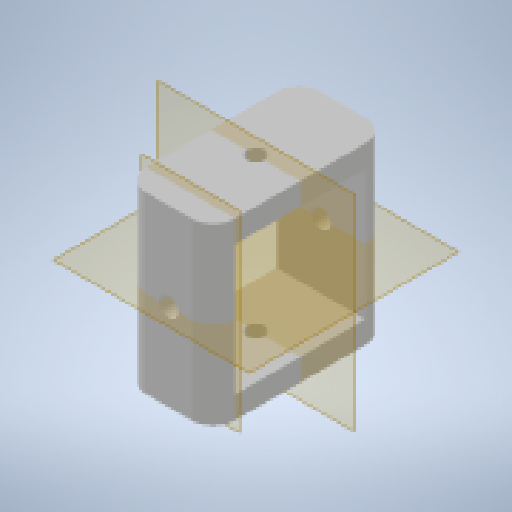
# Autodesk Inventor part: SPIDER GEAR BOX
Saved by Autodesk Inventor 2026.3 (Build 303398000, 398)
## iProperties
Created: 2026-10-21
Part Number: SPIDER GEAR BOX
Material: Generic
Document SubType Name: Modeling
Designer: Salim
Density: 1 g/cm^3
Appearance: Smooth - Red
Author: Salim
Autodesk Inventor part; units mm, degrees
ref_plane "YZ Plane" through (0, 0, 0) normal (1, 0, 0) x (0, 1, 0)
ref_plane "XZ Plane" through (0, 0, 0) normal (0, 1, 0) x (-1, 0, 0)
ref_plane "XY Plane" through (0, 0, 0) normal (0, 0, 1) x (1, 0, 0)
ref_plane "Work Plane5" through (12.266619, -6.690883, -0.784853) normal (0, 0, 1) x (1, 0, 0)
sketch "Sketch1" plane through (12.266619, -6.690883, -0.784853) normal (0, 0, 1) x (1, 0, 0)
  circle A0 centre (-12.266619, 0) radius 2.15
  line L0 (-2.266619, -14.6335) -> (-22.266619, -14.6335)
  line L1 (-22.266619, -14.6335) -> (-22.266619, 14.6335)
  line L2 (-22.266619, 14.6335) -> (-2.266619, 14.6335)
  line L3 (-2.266619, 14.6335) -> (-2.266619, -14.6335)
  line L4 (-2.266619, -14.6335) -> (-22.266619, 14.6335) construction
  line L5 (-22.266619, -14.6335) -> (-2.266619, 14.6335) construction
  arc A1 (-11.792035, 12.257435) -> (-12.741203, 12.257435) centre (-12.266619, 0) ccw
  arc A2 (-12.741203, 12.257435) -> (-14.980664, 11.962604) centre (-12.266619, 0) ccw
  arc A3 (-14.980664, 11.962604) -> (-15.89749, 11.716942) centre (-12.266619, 0) ccw
  arc A4 (-15.89749, 11.716942) -> (-17.984335, 10.852542) centre (-12.266619, 0) ccw
  arc A5 (-17.984335, 10.852542) -> (-18.806338, 10.377958) centre (-12.266619, 0) ccw
  arc A6 (-18.806338, 10.377958) -> (-20.598353, 9.002897) centre (-12.266619, 0) ccw
  arc A7 (-20.598353, 9.002897) -> (-21.269516, 8.331734) centre (-12.266619, 0) ccw
  arc A8 (-21.269516, 8.331734) -> (-22.644577, 6.539719) centre (-12.266619, 0) ccw
  arc A9 (-22.644577, 6.539719) -> (-23.119161, 5.717716) centre (-12.266619, 0) ccw
  arc A10 (-23.119161, 5.717716) -> (-23.983561, 3.630871) centre (-12.266619, 0) ccw
  arc A11 (-23.983561, 3.630871) -> (-24.229223, 2.714045) centre (-12.266619, 0) ccw
  arc A12 (-24.229223, 2.714045) -> (-24.524054, 0.474584) centre (-12.266619, 0) ccw
  arc A13 (-24.524054, 0.474584) -> (-24.524054, -0.474584) centre (-12.266619, 0) ccw
  arc A14 (-24.524054, -0.474584) -> (-24.229223, -2.714045) centre (-12.266619, 0) ccw
  arc A15 (-24.229223, -2.714045) -> (-23.983561, -3.630871) centre (-12.266619, 0) ccw
  arc A16 (-23.983561, -3.630871) -> (-23.119161, -5.717716) centre (-12.266619, 0) ccw
  arc A17 (-23.119161, -5.717716) -> (-22.644577, -6.539719) centre (-12.266619, 0) ccw
  arc A18 (-22.644577, -6.539719) -> (-21.269516, -8.331734) centre (-12.266619, 0) ccw
  arc A19 (-21.269516, -8.331734) -> (-20.598353, -9.002897) centre (-12.266619, 0) ccw
  arc A20 (-20.598353, -9.002897) -> (-18.806338, -10.377958) centre (-12.266619, 0) ccw
  arc A21 (-18.806338, -10.377958) -> (-17.984335, -10.852542) centre (-12.266619, 0) ccw
  arc A22 (-17.984335, -10.852542) -> (-15.89749, -11.716942) centre (-12.266619, 0) ccw
  arc A23 (-15.89749, -11.716942) -> (-14.980664, -11.962604) centre (-12.266619, 0) ccw
  arc A24 (-14.980664, -11.962604) -> (-12.741203, -12.257435) centre (-12.266619, 0) ccw
  arc A25 (-12.741203, -12.257435) -> (-11.792035, -12.257435) centre (-12.266619, 0) ccw
  arc A26 (-11.792035, -12.257435) -> (-9.552574, -11.962604) centre (-12.266619, 0) ccw
  arc A27 (-9.552574, -11.962604) -> (-8.635748, -11.716942) centre (-12.266619, 0) ccw
  arc A28 (-8.635748, -11.716942) -> (-6.548903, -10.852542) centre (-12.266619, 0) ccw
  arc A29 (-6.548903, -10.852542) -> (-5.7269, -10.377958) centre (-12.266619, 0) ccw
  arc A30 (-5.7269, -10.377958) -> (-3.934885, -9.002897) centre (-12.266619, 0) ccw
  arc A31 (-3.934885, -9.002897) -> (-3.263722, -8.331734) centre (-12.266619, 0) ccw
  arc A32 (-3.263722, -8.331734) -> (-1.888661, -6.539719) centre (-12.266619, 0) ccw
  arc A33 (-1.888661, -6.539719) -> (-1.414077, -5.717716) centre (-12.266619, 0) ccw
  arc A34 (-1.414077, -5.717716) -> (-0.549677, -3.630871) centre (-12.266619, 0) ccw
  arc A35 (-0.549677, -3.630871) -> (-0.304015, -2.714045) centre (-12.266619, 0) ccw
  arc A36 (-0.304015, -2.714045) -> (-0.009184, -0.474584) centre (-12.266619, 0) ccw
  arc A37 (-0.009184, -0.474584) -> (-0.009184, 0.474584) centre (-12.266619, 0) ccw
  arc A38 (-0.009184, 0.474584) -> (-0.304015, 2.714045) centre (-12.266619, 0) ccw
  arc A39 (-0.304015, 2.714045) -> (-0.549677, 3.630871) centre (-12.266619, 0) ccw
  arc A40 (-0.549677, 3.630871) -> (-1.414077, 5.717716) centre (-12.266619, 0) ccw
  arc A41 (-1.414077, 5.717716) -> (-1.888661, 6.539719) centre (-12.266619, 0) ccw
  arc A42 (-1.888661, 6.539719) -> (-3.263722, 8.331734) centre (-12.266619, 0) ccw
  arc A43 (-3.263722, 8.331734) -> (-3.934885, 9.002897) centre (-12.266619, 0) ccw
  arc A44 (-3.934885, 9.002897) -> (-5.7269, 10.377958) centre (-12.266619, 0) ccw
  arc A45 (-5.7269, 10.377958) -> (-6.548903, 10.852542) centre (-12.266619, 0) ccw
  arc A46 (-6.548903, 10.852542) -> (-8.635748, 11.716942) centre (-12.266619, 0) ccw
  arc A47 (-8.635748, 11.716942) -> (-9.552574, 11.962604) centre (-12.266619, 0) ccw
  arc A48 (-9.552574, 11.962604) -> (-11.792035, 12.257435) centre (-12.266619, 0) ccw
  point P0 (-12.266619, 0)
  point P1 (-12.266619, 0)
  dimension "d0" = 20
  dimension "d1" = 29.267
  constraints: 96 point on circle, 49 centre point, 12 end point, 3 coincident, 2 midpoint, 1 other
  measures "d0" distance of L1.end L2.end
  measures "d1" distance of L0.end L1.end
extrude "Extrusion1" add sketch "Sketch1" along normal blind 5 contours L0 L1 A18 A19 A20 A21 A22 A23 A24 A25 A26 A27 A28 A29 A30 A31 A32 L3 | A32 A31 A30 A29 A28 A27 A26 A25 A24 A23 A22 A21 A20 A19 A18 L1 A8 A7 A6 A5 A4 A3 A2 A1 A48 A47 A46 A45 A44 A43 A42 L3 | A42 A43 A44 A45 A46 A47 A48 A1 A2 A3 A4 A5 A6 A7 A8 L1 L2 L3
ref_plane "Work Plane2" through (0, -6.690883, -15.418234) normal (0, 0, 1) x (0, -1, 0)
mirror "Mirror1" about plane through (0, -6.690883, -15.418234) normal (0, 0, 1) of "Extrusion1"
sketch "Sketch3" plane through (-10, -21.324383, -0.784853) normal (0, -1, 0) x (1, 0, 0)
  circle A0 centre (10, -14.633381) radius 2
  line L0 (0, 5) -> (20, 5)
  line L1 (0, -34.266762) -> (20, -34.266762)
  line L2 (20, -34.266762) -> (20, 5)
  line L3 (20, 5) -> (0, 5)
  line L4 (0, 5) -> (0, -34.266762)
  line L5 (0, -34.266762) -> (20, 5) construction
  line L6 (20, -34.266762) -> (0, 5) construction
  line L7 (20, -29.266762) -> (0, -29.266762)
  line L8 (20, -29.266762) -> (20, -34.266762)
  line L9 (20, -34.266762) -> (0, -34.266762)
  line L10 (0, -29.266762) -> (0, -34.266762)
  constraints: 12 end point, 2 parallel, 1 centre point, 1 coincident, 1 horizontal, 1 midpoint, 1 perpendicular
extrude "Extrusion2" add sketch "Sketch3" along normal blind 5
ref_plane "Work Plane4" through (0, -6.690883, -15.418234) normal (0, 1, 0) x (0, 0, -1)
mirror "Mirror3" about plane through (0, -6.690883, -15.418234) normal (0, 1, 0) of "Extrusion2"
fillet "Fillet1" radius 5 4 edges at (10, -6.6909, -35.0516) (-10, -6.6909, -35.0516) (10, -6.6909, 4.2151) (-10, -6.6909, 4.2151)
body "Solid1"
